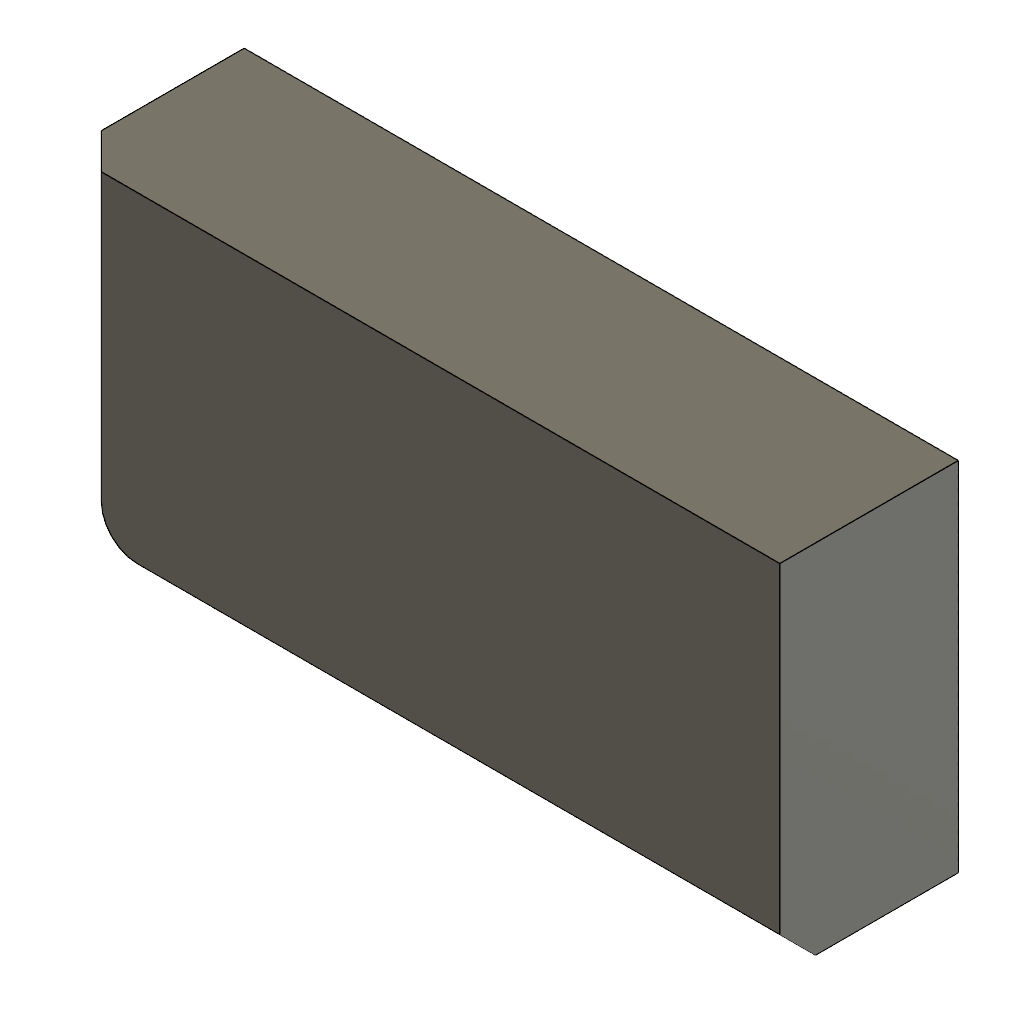
chamfer_and_fillet_adjacent (Autodesk Fusion 360 design; units mm, degrees)
part number: 2026-11-12-22-57-22-737
Autodesk Fusion 360 part; units mm, degrees
sketch "Sketch1" plane through (0, 0, 0) normal (0, 0, 1) x (1, 0, 0)
  line L0 (0, 0) -> (20, 0)
  line L1 (20, 0) -> (20, 10)
  line L2 (20, 10) -> (0, 10)
  line L3 (0, 10) -> (0, 0)
extrude "Extrude1" add sketch "Sketch1" along normal blind 5
fillet "Fillet1" radius 2 1 edges at (0, 0, 2.5)
chamfer "Chamfer1" distance 1 angle 45 3 edges at (11, 0, 5) (0.5858, 0.5858, 5) (0, 6, 5) tangent chain off
